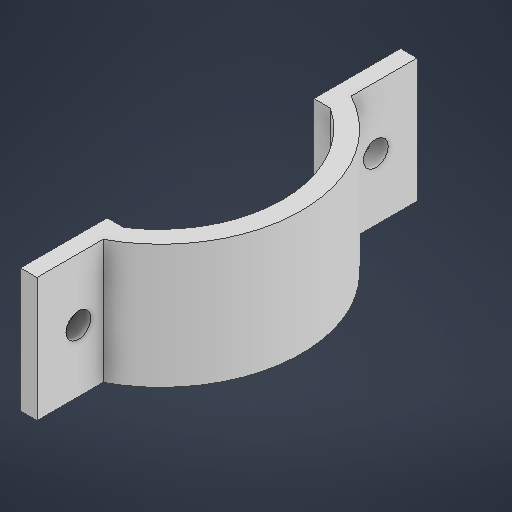
# Autodesk Inventor part: trzymanie_silnika_dol
Saved by Autodesk Inventor 2026.1 (Build 301233020, 233B)
## iProperties
Created: 2026-07-31
Part Number: trzymanie_silnika_dol
Material: Ogólny
Document SubType Name: Modeling
Designer: Nitro
Density: 1 g/cm^3
Appearance: Domyślna
Author: Nitro
Autodesk Inventor part; units mm, degrees
ref_plane "YZ Plane" through (0, 0, 0) normal (1, 0, 0) x (0, 1, 0)
ref_plane "XZ Plane" through (0, 0, 0) normal (0, 1, 0) x (-1, 0, 0)
ref_plane "XY Plane" through (0, 0, 0) normal (0, 0, 1) x (1, 0, 0)
sketch "Szkic1" plane through (0, 0, 0) normal (0, 1, 0) x (-1, 0, 0)
  line L0 (0, 0) -> (2, 0)
  line L1 (2, 0) -> (2, -46)
  line L2 (2, -46) -> (0, -46)
  line L3 (0, -46) -> (0, 0)
  dimension "d0" = 2
  dimension "d1" = 46
  constraints: 8 end point, 2 parallel, 1 horizontal, 1 perpendicular
  measures "d0" distance of L1.end L2.end
  measures "d1" distance of L0.end L1.end
extrude "Wyciągnięcie proste1" add sketch "Szkic1" along normal blind 15
sketch "Szkic2" plane through (0, 0, 0) normal (1, 0, 0) x (0, 0, -1)
  line L0 (0, 0) -> (46, 0) projected
  line L1 (46, 0) -> (46, 15) projected
  line L2 (0, 15) -> (46, 15) projected
  line L3 (0, 0) -> (0, 15) projected
  circle A0 centre (5, 7.5) radius 1.5
  circle A1 centre (41, 7.5) radius 1.5
  dimension "d4" = 5
  dimension "d5" = 5
  dimension "d6" = 7.5
  dimension "d7" = 7.5
  dimension "d8" = 3
  dimension "d9" = 3
  constraints: 2 centre point, 2 coincident
  measures "d4" distance from line of L3 point (5, 7.5)
  measures "d5" distance from line of L1 point (41, 7.5)
  measures "d6" distance from line of L2 point (41, 7.5)
  measures "d7" distance from line of L2 point (5, 7.5)
  measures "d8" diameter of A0
  measures "d9" diameter of A1
extrude "Wyciągnięcie proste2" cut sketch "Szkic2" against normal blind 15 contours A0 | A1
sketch "Szkic3" plane through (0, 0, 0) normal (0, -1, 0) x (1, 0, 0)
  line L0 (0, 0) -> (0, -46) projected
  line L1 (-2, 0) -> (0, 0) projected
  arc A0 (0, -35.5) -> (0, -10.5) centre (-8.2916, -23) ccw
  line L2 (0, -46) -> (-2, -46) projected
  arc A1 (0, -38) -> (0, -8) centre (-8, -23) ccw
  dimension "d12" = 10.5
  dimension "d13" = 10.5
  dimension "d14" = 15
  dimension "d15" = 8
  dimension "d16" = 8
  dimension "d21" = 17
  constraints: 4 point on circle, 4 point on line, 2 centre point
  measures "d12" distance of L0.end A0.start
  measures "d13" distance from line of L1 A0.end
  measures "d14" radius of A0
  measures "d15" distance from line of L2 A1.start
  measures "d16" distance from line of L1 A1.end
  measures "d21" radius of A1
extrude "Wyciągnięcie proste3" add sketch "Szkic3" against normal blind 15 contours A1 L0 A0
sketch "Szkic4" plane through (0, 0, 0) normal (0, -1, 0) x (1, 0, 0)
  line L0 (0, -10.5) -> (0, -35.5) projected
  arc A0 (0, -35.5) -> (0, -10.5) centre (-8.2916, -23) ccw projected
  arc A1 (0, -38) -> (0, -8) centre (-8, -23) ccw projected
  line L1 (0, 0) -> (0, -8) projected
  line L2 (-2, 0) -> (0, 0) projected
  line L3 (-2, -46) -> (-2, 0) projected
  line L4 (0, -46) -> (-2, -46) projected
  line L5 (0, -38) -> (0, -46) projected
  line L6 (0, -10.5) -> (-2, -10.5)
  line L7 (0, -35.5) -> (-2, -35.5)
  constraints: 4 end point, 2 perpendicular, 2 point on line
extrude "Wyciągnięcie proste4" cut sketch "Szkic4" against normal blind 15 contours L0 L7 L3 L6
